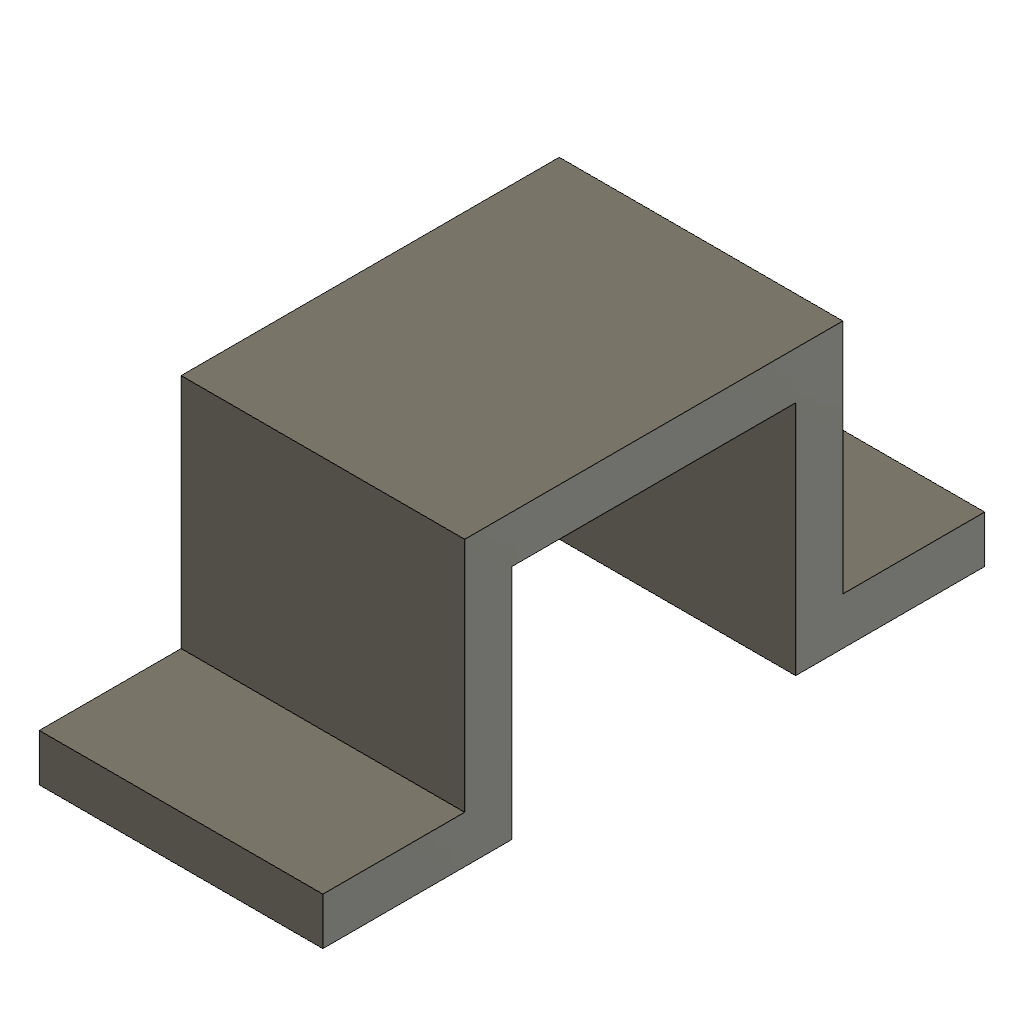
Motor Brackets (Autodesk Fusion 360 design; units mm, degrees)
part number: 2026-11-04-19-36-20-616
Autodesk Fusion 360 part; units mm, degrees
sketch "Sketch1" plane through (0, 0, 0) normal (1, 0, 0) x (0, 0, -1)
  line L0 (-6, 0) -> (6, 0)
  line L1 (6, 0) -> (6, 10)
  line L2 (6, 10) -> (-6, 10)
  line L3 (-6, 10) -> (-6, 0)
  line L4 (-6, 0) -> (-8, 0)
  line L5 (-8, 0) -> (-8, 12)
  line L6 (-8, 12) -> (-6, 12)
  line L7 (-6, 12) -> (-6, 0)
  line L8 (8, 12) -> (-6, 12)
  line L9 (-6, 12) -> (-6, 10)
  line L10 (-6, 10) -> (8, 10)
  line L11 (8, 10) -> (8, 12)
  line L12 (8, 0) -> (6, 0)
  line L13 (6, 0) -> (6, 10)
  line L14 (6, 10) -> (8, 10)
  line L15 (8, 10) -> (8, 0)
  line L16 (8, 0) -> (14, 0)
  line L17 (14, 0) -> (14, 2)
  line L18 (14, 2) -> (8, 2)
  line L19 (8, 2) -> (8, 0)
  line L20 (-8, 0) -> (-14, 0)
  line L21 (-14, 0) -> (-14, 2)
  line L22 (-14, 2) -> (-8, 2)
  line L23 (-8, 2) -> (-8, 0)
  dimension "d1" = 12
  dimension "d2" = 10
  constraint horizontal L0
  constraint vertical L1
  constraint horizontal L2
  constraint vertical L3
  constraint horizontal L4
  constraint vertical L5
  constraint horizontal L6
  constraint vertical L7
  constraint horizontal L8
  constraint vertical L9
  constraint horizontal L10
  constraint vertical L11
  constraint horizontal L12
  constraint vertical L13
  constraint horizontal L14
  constraint vertical L15
  constraint horizontal L16
  constraint vertical L17
  constraint horizontal L18
  constraint vertical L19
  constraint horizontal L20
  constraint vertical L21
  constraint horizontal L22
  constraint vertical L23
  measures "d1" distance of L0.start L0.end
  measures "d2" distance of L0.start L2.end
extrude "Extrude1" add sketch "Sketch1" along normal blind 12 contours L3 L4 L5 L6 L7 L9 L23 | L1 L10 L12 L13 L14 L15 L19 | L2 L7 L8 L9 L10 L11 L14 | L5 L20 L21 L22 L23 | L15 L16 L17 L18 L19
